Autodesk Inventor part; units mm, degrees
(part 2 of 2)
  arc A203 (9.9592, -17.344) -> (10.9322, -16.7477) centre (0, 0) ccw
  arc A204 (12.5498, -15.5725) -> (10.9322, -16.7477) centre (11.7557, -16.1803) ccw
  arc A205 (12.5498, -15.5725) -> (13.4176, -14.8313) centre (0, 0) ccw
  arc A206 (14.8313, -13.4176) -> (13.4176, -14.8313) centre (14.1421, -14.1421) ccw
  arc A207 (14.8313, -13.4176) -> (15.5725, -12.5498) centre (0, 0) ccw
  arc A208 (16.7477, -10.9322) -> (15.5725, -12.5498) centre (16.1803, -11.7557) ccw
  arc A209 (16.7477, -10.9322) -> (17.344, -9.9592) centre (0, 0) ccw
  arc A210 (18.2517, -8.1777) -> (17.344, -9.9592) centre (17.8201, -9.0798) ccw
  arc A211 (18.2517, -8.1777) -> (18.6884, -7.1234) centre (0, 0) ccw
  arc A212 (19.3063, -5.2219) -> (18.6884, -7.1234) centre (19.0211, -6.1803) ccw
  arc A213 (19.3063, -5.2219) -> (19.5727, -4.1122) centre (0, 0) ccw
  arc A214 (19.8855, -2.1374) -> (19.5727, -4.1122) centre (19.7538, -3.1287) ccw
  arc A215 (19.8855, -2.1374) -> (19.975, -0.9997) centre (0, 0) ccw
  arc A216 (19.975, 0.9997) -> (19.975, -0.9997) centre (20, 0) ccw
  arc A217 (19.975, 0.9997) -> (19.8855, 2.1374) centre (0, 0) ccw
  arc A218 (19.5727, 4.1122) -> (19.8855, 2.1374) centre (19.7538, 3.1287) ccw
  arc A219 (19.5727, 4.1122) -> (19.3063, 5.2219) centre (0, 0) ccw
  arc A220 (18.6884, 7.1234) -> (19.3063, 5.2219) centre (19.0211, 6.1803) ccw
  arc A221 (18.6884, 7.1234) -> (18.2517, 8.1777) centre (0, 0) ccw
  arc A222 (17.344, 9.9592) -> (18.2517, 8.1777) centre (17.8201, 9.0798) ccw
  arc A223 (17.344, 9.9592) -> (16.7477, 10.9322) centre (0, 0) ccw
  arc A224 (15.5725, 12.5498) -> (16.7477, 10.9322) centre (16.1803, 11.7557) ccw
  arc A225 (15.5725, 12.5498) -> (14.8313, 13.4176) centre (0, 0) ccw
  arc A226 (13.4176, 14.8313) -> (14.8313, 13.4176) centre (14.1421, 14.1421) ccw
  arc A227 (13.4176, 14.8313) -> (12.5498, 15.5725) centre (0, 0) ccw
  arc A228 (10.9322, 16.7477) -> (12.5498, 15.5725) centre (11.7557, 16.1803) ccw
  arc A229 (10.9322, 16.7477) -> (9.9592, 17.344) centre (0, 0) ccw
  arc A230 (8.1777, 18.2517) -> (9.9592, 17.344) centre (9.0798, 17.8201) ccw
  arc A231 (8.1777, 18.2517) -> (7.1234, 18.6884) centre (0, 0) ccw
  arc A232 (5.2219, 19.3063) -> (7.1234, 18.6884) centre (6.1803, 19.0211) ccw
  arc A233 (5.2219, 19.3063) -> (4.1122, 19.5727) centre (0, 0) ccw
  arc A234 (2.1374, 19.8855) -> (4.1122, 19.5727) centre (3.1287, 19.7538) ccw
  arc A235 (2.1374, 19.8855) -> (0.9997, 19.975) centre (0, 0) ccw
  arc A236 (-0.9997, 19.975) -> (0.9997, 19.975) centre (0, 20) ccw
  arc A237 (-0.9997, 19.975) -> (-2.1374, 19.8855) centre (0, 0) ccw
  arc A238 (-4.1122, 19.5727) -> (-2.1374, 19.8855) centre (-3.1287, 19.7538) ccw
  arc A239 (-4.1122, 19.5727) -> (-5.2219, 19.3063) centre (0, 0) ccw
  arc A240 (-7.1234, 18.6884) -> (-5.2219, 19.3063) centre (-6.1803, 19.0211) ccw
  arc A241 (-7.1234, 18.6884) -> (-8.1777, 18.2517) centre (0, 0) ccw
  arc A242 (-9.9592, 17.344) -> (-8.1777, 18.2517) centre (-9.0798, 17.8201) ccw
  arc A243 (-9.9592, 17.344) -> (-10.9322, 16.7477) centre (0, 0) ccw
  arc A244 (-12.5498, 15.5725) -> (-10.9322, 16.7477) centre (-11.7557, 16.1803) ccw
  arc A245 (-12.5498, 15.5725) -> (-13.4176, 14.8313) centre (0, 0) ccw
  arc A246 (-14.8313, 13.4176) -> (-13.4176, 14.8313) centre (-14.1421, 14.1421) ccw
  arc A247 (-14.8313, 13.4176) -> (-15.5725, 12.5498) centre (0, 0) ccw
  arc A248 (-16.7477, 10.9322) -> (-15.5725, 12.5498) centre (-16.1803, 11.7557) ccw
  arc A249 (-16.7477, 10.9322) -> (-17.344, 9.9592) centre (0, 0) ccw
  arc A250 (-18.2517, 8.1777) -> (-17.344, 9.9592) centre (-17.8201, 9.0798) ccw
  arc A251 (-18.2517, 8.1777) -> (-18.6884, 7.1234) centre (0, 0) ccw
  arc A252 (-19.3063, 5.2219) -> (-18.6884, 7.1234) centre (-19.0211, 6.1803) ccw
  arc A253 (-19.3063, 5.2219) -> (-19.5727, 4.1122) centre (0, 0) ccw
  arc A254 (-19.8855, 2.1374) -> (-19.5727, 4.1122) centre (-19.7538, 3.1287) ccw
  arc A255 (-19.8855, 2.1374) -> (-19.975, 0.9997) centre (0, 0) ccw
  arc A256 (-19.975, -0.9997) -> (-19.975, 0.9997) centre (-20, 0) ccw
  line L43 (-5.6144, 12.9244) -> (-5.238, 12.2725)
  arc A257 (-5.238, 12.2725) -> (-4.0481, 11.8264) centre (-4.372, 12.7725) ccw
  arc A258 (4.0481, 11.8264) -> (-4.0481, 11.8264) centre (0, 0) ccw
  arc A259 (4.0481, 11.8264) -> (5.238, 12.2725) centre (4.372, 12.7725) ccw
  line L44 (5.238, 12.2725) -> (5.6144, 12.9244)
  arc A260 (5.6144, 12.9244) -> (5.2483, 14.2904) centre (4.7483, 13.4244) ccw
  line L45 (5.2483, 14.2904) -> (4.9019, 14.4904)
  arc A261 (4.5359, 15.8564) -> (4.9019, 14.4904) centre (5.4019, 15.3564) ccw
  line L46 (4.5359, 15.8564) -> (4.7359, 16.2028)
  arc A262 (6.1019, 16.5688) -> (4.7359, 16.2028) centre (5.6019, 15.7028) ccw
  line L47 (6.1019, 16.5688) -> (11.2981, 13.5688)
  arc A263 (11.6641, 12.2028) -> (11.2981, 13.5688) centre (10.7981, 12.7028) ccw
  line L48 (11.6641, 12.2028) -> (11.4641, 11.8564)
  arc A264 (10.0981, 11.4904) -> (11.4641, 11.8564) centre (10.5981, 12.3564) ccw
  line L49 (10.0981, 11.4904) -> (9.7517, 11.6904)
  arc A265 (9.7517, 11.6904) -> (8.3856, 11.3244) centre (9.2517, 10.8244) ccw
  line L50 (8.3856, 11.3244) -> (8.0093, 10.6725)
  arc A266 (8.0093, 10.6725) -> (8.2179, 9.419) centre (8.8753, 10.1725) ccw
  arc A267 (12.266, 2.4074) -> (8.2179, 9.419) centre (0, 0) ccw
  arc A268 (12.266, 2.4074) -> (13.2473, 1.6) centre (13.2473, 2.6) ccw
  line L51 (13.2473, 1.6) -> (14, 1.6)
  arc A269 (14, 1.6) -> (15, 2.6) centre (14, 2.6) ccw
  line L52 (15, 2.6) -> (15, 3)
  arc A270 (16, 4) -> (15, 3) centre (16, 3) ccw
  line L53 (16, 4) -> (16.4, 4)
  arc A271 (17.4, 3) -> (16.4, 4) centre (16.4, 3) ccw
  line L54 (17.4, 3) -> (17.4, -3)
  arc A272 (16.4, -4) -> (17.4, -3) centre (16.4, -3) ccw
  line L55 (16.4, -4) -> (16, -4)
  arc A273 (15, -3) -> (16, -4) centre (16, -3) ccw
  line L56 (15, -3) -> (15, -2.6)
  arc A274 (15, -2.6) -> (14, -1.6) centre (14, -2.6) ccw
  line L57 (14, -1.6) -> (13.2473, -1.6)
  arc A275 (13.2473, -1.6) -> (12.266, -2.4074) centre (13.2473, -2.6) ccw
  arc A276 (8.2179, -9.419) -> (12.266, -2.4074) centre (0, 0) ccw
  arc A277 (8.2179, -9.419) -> (8.0093, -10.6725) centre (8.8753, -10.1725) ccw
  line L58 (8.0093, -10.6725) -> (8.3856, -11.3244)
  arc A278 (8.3856, -11.3244) -> (9.7517, -11.6904) centre (9.2517, -10.8244) ccw
  line L59 (9.7517, -11.6904) -> (10.0981, -11.4904)
  arc A279 (11.4641, -11.8564) -> (10.0981, -11.4904) centre (10.5981, -12.3564) ccw
  line L60 (11.4641, -11.8564) -> (11.6641, -12.2028)
  arc A280 (11.2981, -13.5688) -> (11.6641, -12.2028) centre (10.7981, -12.7028) ccw
  line L61 (11.2981, -13.5688) -> (6.1019, -16.5688)
  arc A281 (4.7359, -16.2028) -> (6.1019, -16.5688) centre (5.6019, -15.7028) ccw
  line L62 (4.7359, -16.2028) -> (4.5359, -15.8564)
  arc A282 (4.9019, -14.4904) -> (4.5359, -15.8564) centre (5.4019, -15.3564) ccw
  line L63 (4.9019, -14.4904) -> (5.2483, -14.2904)
  arc A283 (5.2483, -14.2904) -> (5.6144, -12.9244) centre (4.7483, -13.4244) ccw
  line L64 (5.6144, -12.9244) -> (5.238, -12.2725)
  arc A284 (5.238, -12.2725) -> (4.0481, -11.8264) centre (4.372, -12.7725) ccw
  arc A285 (-4.0481, -11.8264) -> (4.0481, -11.8264) centre (0, 0) ccw
  arc A286 (-4.0481, -11.8264) -> (-5.238, -12.2725) centre (-4.372, -12.7725) ccw
  line L65 (-5.238, -12.2725) -> (-5.6144, -12.9244)
  arc A287 (-5.6144, -12.9244) -> (-5.2483, -14.2904) centre (-4.7483, -13.4244) ccw
  line L66 (-5.2483, -14.2904) -> (-4.9019, -14.4904)
  arc A288 (-4.5359, -15.8564) -> (-4.9019, -14.4904) centre (-5.4019, -15.3564) ccw
  line L67 (-4.5359, -15.8564) -> (-4.7359, -16.2028)
  arc A289 (-6.1019, -16.5688) -> (-4.7359, -16.2028) centre (-5.6019, -15.7028) ccw
  line L68 (-6.1019, -16.5688) -> (-11.2981, -13.5688)
  arc A290 (-11.6641, -12.2028) -> (-11.2981, -13.5688) centre (-10.7981, -12.7028) ccw
  line L69 (-11.6641, -12.2028) -> (-11.4641, -11.8564)
  arc A291 (-10.0981, -11.4904) -> (-11.4641, -11.8564) centre (-10.5981, -12.3564) ccw
  line L70 (-10.0981, -11.4904) -> (-9.7517, -11.6904)
  arc A292 (-9.7517, -11.6904) -> (-8.3856, -11.3244) centre (-9.2517, -10.8244) ccw
  line L71 (-8.3856, -11.3244) -> (-8.0093, -10.6725)
  arc A293 (-8.0093, -10.6725) -> (-8.2179, -9.419) centre (-8.8753, -10.1725) ccw
  arc A294 (-12.266, -2.4074) -> (-8.2179, -9.419) centre (0, 0) ccw
  arc A295 (-12.266, -2.4074) -> (-13.2473, -1.6) centre (-13.2473, -2.6) ccw
  line L72 (-13.2473, -1.6) -> (-14, -1.6)
  arc A296 (-14, -1.6) -> (-15, -2.6) centre (-14, -2.6) ccw
  line L73 (-15, -2.6) -> (-15, -3)
  arc A297 (-16, -4) -> (-15, -3) centre (-16, -3) ccw
  line L74 (-16, -4) -> (-16.4, -4)
  arc A298 (-17.4, -3) -> (-16.4, -4) centre (-16.4, -3) ccw
  line L75 (-17.4, -3) -> (-17.4, 3)
  arc A299 (-16.4, 4) -> (-17.4, 3) centre (-16.4, 3) ccw
  line L76 (-16.4, 4) -> (-16, 4)
  arc A300 (-15, 3) -> (-16, 4) centre (-16, 3) ccw
  line L77 (-15, 3) -> (-15, 2.6)
  arc A301 (-15, 2.6) -> (-14, 1.6) centre (-14, 2.6) ccw
  line L78 (-14, 1.6) -> (-13.2473, 1.6)
  arc A302 (-13.2473, 1.6) -> (-12.266, 2.4074) centre (-13.2473, 2.6) ccw
  arc A303 (-8.2179, 9.419) -> (-12.266, 2.4074) centre (0, 0) ccw
  arc A304 (-8.2179, 9.419) -> (-8.0093, 10.6725) centre (-8.8753, 10.1725) ccw
  line L79 (-8.0093, 10.6725) -> (-8.3856, 11.3244)
  arc A305 (-8.3856, 11.3244) -> (-9.7517, 11.6904) centre (-9.2517, 10.8244) ccw
  line L80 (-9.7517, 11.6904) -> (-10.0981, 11.4904)
  arc A306 (-11.4641, 11.8564) -> (-10.0981, 11.4904) centre (-10.5981, 12.3564) ccw
  line L81 (-11.4641, 11.8564) -> (-11.6641, 12.2028)
  arc A307 (-11.2981, 13.5688) -> (-11.6641, 12.2028) centre (-10.7981, 12.7028) ccw
  line L82 (-11.2981, 13.5688) -> (-6.1019, 16.5688)
  arc A308 (-4.7359, 16.2028) -> (-6.1019, 16.5688) centre (-5.6019, 15.7028) ccw
  line L83 (-4.7359, 16.2028) -> (-4.5359, 15.8564)
  arc A309 (-4.9019, 14.4904) -> (-4.5359, 15.8564) centre (-5.4019, 15.3564) ccw
  line L84 (-4.9019, 14.4904) -> (-5.2483, 14.2904)
  arc A310 (-5.2483, 14.2904) -> (-5.6144, 12.9244) centre (-4.7483, 13.4244) ccw
  circle A311 centre (0, 0) radius 21.5
  circle A312 centre (-21.5, 0) radius 1
  circle A313 centre (-21.2353, -3.3633) radius 1
  circle A314 centre (-20.4477, -6.6439) radius 1
  circle A315 centre (-19.1566, -9.7608) radius 1
  circle A316 centre (-17.3939, -12.6374) radius 1
  circle A317 centre (-15.2028, -15.2028) radius 1
  circle A318 centre (-12.6374, -17.3939) radius 1
  circle A319 centre (-9.7608, -19.1566) radius 1
  circle A320 centre (-6.6439, -20.4477) radius 1
  circle A321 centre (-3.3633, -21.2353) radius 1
  circle A322 centre (0, -21.5) radius 1
  circle A323 centre (3.3633, -21.2353) radius 1
  circle A324 centre (6.6439, -20.4477) radius 1
  circle A325 centre (9.7608, -19.1566) radius 1
  circle A326 centre (12.6374, -17.3939) radius 1
  circle A327 centre (15.2028, -15.2028) radius 1
  circle A328 centre (17.3939, -12.6374) radius 1
  circle A329 centre (19.1566, -9.7608) radius 1
  circle A330 centre (20.4477, -6.6439) radius 1
  circle A331 centre (21.2353, -3.3633) radius 1
  circle A332 centre (21.5, 0) radius 1
  circle A333 centre (21.2353, 3.3633) radius 1
  circle A334 centre (20.4477, 6.6439) radius 1
  circle A335 centre (19.1566, 9.7608) radius 1
  circle A336 centre (17.3939, 12.6374) radius 1
  circle A337 centre (15.2028, 15.2028) radius 1
  circle A338 centre (12.6374, 17.3939) radius 1
  circle A339 centre (9.7608, 19.1566) radius 1
  circle A340 centre (6.6439, 20.4477) radius 1
  circle A341 centre (3.3633, 21.2353) radius 1
  circle A342 centre (0, 21.5) radius 1
  circle A343 centre (-3.3633, 21.2353) radius 1
  circle A344 centre (-6.6439, 20.4477) radius 1
  circle A345 centre (-9.7608, 19.1566) radius 1
  circle A346 centre (-12.6374, 17.3939) radius 1
  circle A347 centre (-15.2028, 15.2028) radius 1
  circle A348 centre (-17.3939, 12.6374) radius 1
  circle A349 centre (-19.1566, 9.7608) radius 1
  circle A350 centre (-20.4477, 6.6439) radius 1
  circle A351 centre (-21.2353, 3.3633) radius 1
  point P0 (-7.9821, 103.4477)
  point P1 (-9.3959, 102.0339)
  point P2 (-14.9794, 88.5542)
  point P3 (-14.9794, 86.5547)
  point P4 (-14.8714, 85.1822)
  point P5 (-14.5586, 83.2073)
  point P6 (-14.2372, 81.8686)
  point P7 (-13.6193, 79.967)
  point P8 (-13.0924, 78.695)
  point P9 (-12.1847, 76.9134)
  point P10 (-11.4653, 75.7395)
  point P11 (-10.2901, 74.1219)
  point P12 (-9.3959, 73.075)
  point P13 (-7.9821, 71.6612)
  point P14 (-6.9352, 70.767)
  point P15 (-5.3176, 69.5918)
  point P16 (-4.1437, 68.8724)
  point P17 (-2.3621, 67.9647)
  point P18 (-1.0901, 67.4378)
  point P19 (0.8115, 66.8199)
  point P20 (2.1502, 66.4985)
  point P21 (4.1251, 66.1857)
  point P22 (5.4976, 66.0777)
  point P23 (7.4971, 66.0777)
  point P24 (8.8696, 66.1857)
  point P25 (10.8445, 66.4985)
  point P26 (12.1832, 66.8199)
  point P27 (14.0848, 67.4378)
  point P28 (15.3568, 67.9647)
  point P29 (17.1384, 68.8724)
  point P30 (18.3123, 69.5918)
  point P31 (19.9299, 70.767)
  point P32 (20.9768, 71.6612)
  point P33 (22.3906, 73.075)
  point P34 (23.2848, 74.1219)
  point P35 (24.46, 75.7395)
  point P36 (25.1794, 76.9134)
  point P37 (26.0871, 78.695)
  point P38 (27.2319, 81.8686)
  point P39 (26.614, 79.967)
  point P40 (27.5533, 83.2073)
  point P41 (27.8661, 85.1822)
  point P42 (27.9741, 88.5542)
  point P43 (27.9741, 86.5547)
  point P44 (27.8661, 89.9267)
  point P45 (27.5533, 91.9016)
  point P46 (27.2319, 93.2403)
  point P47 (26.614, 95.1419)
  point P48 (26.0871, 96.4139)
  point P49 (25.1794, 98.1954)
  point P50 (24.46, 99.3694)
  point P51 (23.2848, 100.987)
  point P52 (22.3906, 102.0339)
  point P53 (20.9768, 103.4477)
  point P54 (19.9299, 104.3419)
  point P55 (18.3123, 105.5171)
  point P56 (17.1384, 106.2365)
  point P57 (15.3568, 107.1442)
  point P58 (14.0848, 107.6711)
  point P59 (12.1832, 108.289)
  point P60 (10.8445, 108.6104)
  point P61 (8.8696, 108.9232)
  point P62 (7.4971, 109.0312)
  point P63 (5.4976, 109.0312)
  point P64 (4.1251, 108.9232)
  point P65 (2.1502, 108.6104)
  point P66 (0.8115, 108.289)
  point P67 (-1.0901, 107.6711)
  point P68 (-2.3621, 107.1442)
  point P69 (-4.1437, 106.2365)
  point P70 (-5.3176, 105.5171)
  point P71 (-6.9352, 104.3419)
  point P72 (-10.2901, 100.987)
  point P73 (-11.4653, 99.3694)
  point P74 (-12.1847, 98.1954)
  point P75 (-13.0924, 96.4139)
  point P76 (-13.6193, 95.1419)
  point P77 (-14.2372, 93.2403)
  point P78 (-14.5586, 91.9016)
  point P79 (-14.8714, 89.9267)
  point P80 (15.8933, 14.4794)
  point P81 (14.4794, 15.8933)
  point P82 (13.4325, 16.7874)
  point P83 (11.8149, 17.9627)
  point P84 (10.641, 18.6821)
  point P85 (8.8595, 19.5898)
  point P86 (7.5875, 20.1167)
  point P87 (5.6859, 20.7345)
  point P88 (4.3471, 21.0559)
  point P89 (2.3723, 21.3687)
  point P90 (0.9997, 21.4767)
  point P91 (-0.9997, 21.4767)
  point P92 (-2.3723, 21.3687)
  point P93 (-4.3471, 21.0559)
  point P94 (-5.6859, 20.7345)
  point P95 (-7.5875, 20.1167)
  point P96 (-8.8595, 19.5898)
  point P97 (-10.641, 18.6821)
  point P98 (-11.8149, 17.9627)
  point P99 (-13.4325, 16.7874)
  point P100 (-14.4794, 15.8933)
  point P101 (-15.8933, 14.4794)
  point P102 (-16.7874, 13.4325)
  point P103 (-17.9627, 11.8149)
  point P104 (-18.6821, 10.641)
  point P105 (-19.5898, 8.8595)
  point P106 (-20.1167, 7.5875)
  point P107 (-20.7345, 5.6859)
  point P108 (-21.0559, 4.3471)
  point P109 (-21.3687, 2.3723)
  point P110 (-21.4767, 0.9997)
  point P111 (-21.4767, -0.9997)
  point P112 (-21.3687, -2.3723)
  point P113 (-21.0559, -4.3471)
  point P114 (-20.7345, -5.6859)
  point P115 (-20.1167, -7.5875)
  point P116 (-19.5898, -8.8595)
  point P117 (-18.6821, -10.641)
  point P118 (-17.9627, -11.8149)
  point P119 (-16.7874, -13.4325)
  point P120 (-15.8933, -14.4794)
  point P121 (-14.4794, -15.8933)
  point P122 (-13.4325, -16.7874)
  point P123 (-11.8149, -17.9627)
  point P124 (-10.641, -18.6821)
  point P125 (-8.8595, -19.5898)
  point P126 (-7.5875, -20.1167)
  point P127 (-5.6859, -20.7345)
  point P128 (-4.3471, -21.0559)
  point P129 (-2.3723, -21.3687)
  point P130 (-0.9997, -21.4767)
  point P131 (0.9997, -21.4767)
  point P132 (2.3723, -21.3687)
  point P133 (4.3471, -21.0559)
  point P134 (5.6859, -20.7345)
  point P135 (7.5875, -20.1167)
  point P136 (8.8595, -19.5898)
  point P137 (10.641, -18.6821)
  point P138 (11.8149, -17.9627)
  point P139 (13.4325, -16.7874)
  point P140 (14.4794, -15.8933)
  point P141 (15.8933, -14.4794)
  point P142 (16.7874, -13.4325)
  point P143 (17.9627, -11.8149)
  point P144 (18.6821, -10.641)
  point P145 (19.5898, -8.8595)
  point P146 (20.1167, -7.5875)
  point P147 (20.7345, -5.6859)
  point P148 (21.0559, -4.3471)
  point P149 (21.3687, -2.3723)
  point P150 (21.4767, -0.9997)
  point P151 (21.4767, 0.9997)
  point P152 (21.3687, 2.3723)
  point P153 (21.0559, 4.3471)
  point P154 (20.7345, 5.6859)
  point P155 (20.1167, 7.5875)
  point P156 (19.5898, 8.8595)
  point P157 (18.6821, 10.641)
  point P158 (17.9627, 11.8149)
  point P159 (16.7874, 13.4325)
  dimension "d92" = 43
  dimension "d97" = 43
  dimension "d93" = 2
  dimension "d94" = 360
  dimension "d98" = 2
  dimension "d99" = 360
  constraints: 536 point on circle, 348 centre point, 168 end point, 2 coincident, 1 horizontal alignment, 166 other
  measures "d93" diameter of A135
  measures "d98" diameter of A312
extrude "Extrusion18" add sketch "Skizze18" against normal up to surface (10 mm away) contours A332 A311 A331 A330 A329 A328 A327 A326 A325 A324 A323 A322 A321 A320 A319 A318 A317 A316 A315 A314 A313 A312 A351 A350 A349 A348 A347 A346 A345 A344 A343 A342 A341 A340 A339 A338 A337 A336 A335 A334 A333 bodies 3
equation "\"d55\" = 0.5 * d53"
equation "\"d61\" = 0.5 * d60"
